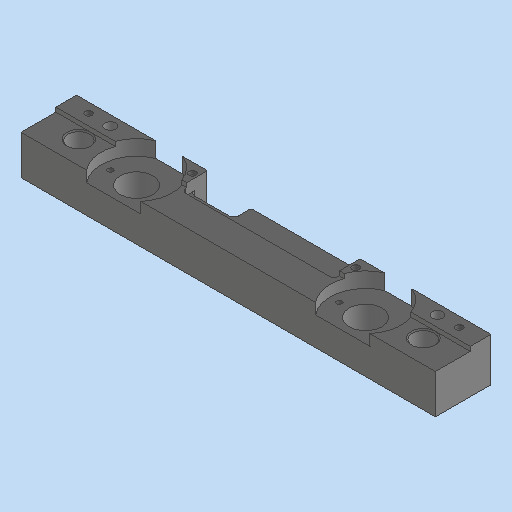
# Autodesk Inventor part: MM0937AN100_G16_150
Saved by Autodesk Inventor 2023.3 (Build 273359000, 359)
## iProperties
Created: 2024-03-12
Part Number: MM0937AN100_G16_150
Material: 1.2379 X155CrVMo12-1
Description: =<RBPARTNOTITLE2>
Document SubType Name: Modeling
Designer: FSM9BW
Mass: 534.69 g
Surface Area: 204.971 cm^2
Volume: 68.1134 cm^3
Density: 7.85 g/cm^3
Appearance: Stahl - rostfrei AnP
RBPARTMADEOF: 20 x 25,5 x 190 (FM)
RBDRAWINGMISSINGSPEC: --
AnP_Kategorie: 1
RBPARTNOTITLE2: Anfertigungsteil
RBSURFACE: plasma nitrided 1000 HV, Nht 0,1 + 0,1
RBPARTNOTITLE1: manufactured part
RBSURFACE2: plasmanitriert 1000 HV, Nht 0,1 + 0,1
AnP_Material: =<Material>
RBMATERIAL: =<Material>
RBMATNO: =<Part Number>
RBPARTNO: SIEHE MNR
MaxAbmaße: 20 x 25,5 x 190 (FM)
Author: FSM9BW
Keywords: =<RBPARTMADEOF>
Comments: =<RBSURFACE2>
Revision Number: 01
Autodesk Inventor part; units mm, degrees
ref_plane "YZ Plane" through (0, 0, 0) normal (1, 0, 0) x (0, 1, 0)
ref_plane "XZ Plane" through (0, 0, 0) normal (0, 1, 0) x (-1, 0, 0)
ref_plane "XY Plane" through (0, 0, 0) normal (0, 0, 1) x (1, 0, 0)
sketch "Skizze1" plane through (0, 0, 0) normal (0, 0, 1) x (1, 0, 0)
  line L0 (-95, 0) -> (95, 0)
  line L1 (95, 0) -> (95, 25.5)
  line L2 (95, 25.5) -> (-95, 25.5)
  line L3 (-95, 25.5) -> (-95, 0)
  line L4 (-133, 0) -> (133, 0) projected
  line L5 (0, -5.1) -> (0, 30.6) projected
  point P0 (0, 0)
  dimension "d0" = 190
  dimension "d1" = 25.5
  constraints: 8 end point, 2 parallel, 1 collinear, 1 horizontal, 1 perpendicular, 1 other
  measures "d0" distance of L0.start L0.end
  measures "d1" distance of L2.end L0.start
extrude "Extrusion1" add sketch "Skizze1" along normal mid plane 20
sketch "Skizze2" plane through (0, 0, 10) normal (0, 0, 1) x (1, 0, 0)
  line L0 (-95, 25.5) -> (-95, 0) projected
  line L1 (-95, 0) -> (95, 0) projected
  line L2 (95, 0) -> (95, 25.5) projected
  line L3 (95, 25.5) -> (-95, 25.5) projected
  line L4 (-35, 25.5) -> (35, 25.5)
  line L5 (35, 25.5) -> (35, 13.5)
  line L6 (35, 13.5) -> (-35, 13.5)
  line L7 (-35, 13.5) -> (-35, 25.5)
  line L8 (0, -5.1) -> (0, 30.6) projected
  point P0 (0, 0)
  dimension "d4" = 70
  dimension "d5" = 12
  constraints: 8 end point, 2 parallel, 1 horizontal, 1 perpendicular, 1 point on line, 1 other
  measures "d4" distance of L5.end L6.end
  measures "d5" distance of L6.end L4.start
extrude "Extrusion2" cut sketch "Skizze2" against normal blind 5 contours L3 L8 L6 L7 | L3 L5 L6 L8
sketch "Skizze3" plane through (0, 0, 10) normal (0, 0, 1) x (1, 0, 0)
  line L0 (35, 25.5) -> (35, 13.5) projected
  line L1 (35, 13.5) -> (-35, 13.5) projected
  line L2 (-35, 13.5) -> (-35, 25.5) projected
  line L3 (-35, 25.5) -> (-95, 25.5) projected
  line L4 (-95, 25.5) -> (-95, 0) projected
  line L5 (-95, 0) -> (95, 0) projected
  line L6 (95, 0) -> (95, 25.5) projected
  line L7 (95, 25.5) -> (35, 25.5) projected
  line L8 (-35, 25.5) -> (-15, 25.5)
  line L9 (-15, 25.5) -> (-15, 17.5)
  line L10 (-15, 17.5) -> (-35, 17.5)
  line L11 (-35, 17.5) -> (-35, 25.5)
  point P0 (0, 0)
  point P1 (-35, 17.5)
  dimension "d8" = 8
  dimension "d9" = 60
  dimension "d10" = 20
  constraints: 8 end point, 2 parallel, 1 horizontal, 1 perpendicular, 1 point on line
  measures "d8" distance of L10.end L8.start
  measures "d9" distance between parallel lines of L11 L4
  measures "d10" distance between parallel lines of L2 L9
extrude "Extrusion3" cut sketch "Skizze3" against normal through all contours L2 L8 L9 L10
sketch "Skizze4" plane through (0, 0, 10) normal (0, 0, 1) x (1, 0, 0)
  line L0 (35, 25.5) -> (35, 13.5) projected
  line L1 (35, 13.5) -> (-35, 13.5) projected
  line L2 (-35, 13.5) -> (-35, 25.5) projected
  line L3 (-35, 25.5) -> (-95, 25.5) projected
  line L4 (-95, 25.5) -> (-95, 0) projected
  line L5 (-95, 0) -> (95, 0) projected
  line L6 (95, 0) -> (95, 25.5) projected
  line L7 (95, 25.5) -> (35, 25.5) projected
  line L8 (-95, 0) -> (95, 0)
  line L9 (95, 0) -> (95, 16)
  line L10 (95, 16) -> (-95, 16)
  line L11 (-95, 16) -> (-95, 0)
  point P0 (0, 0)
  point P1 (-35, 10.5)
  point P2 (35, 10.5)
  dimension "d13" = 190
  dimension "d14" = 16
  constraints: 8 end point, 2 parallel, 1 horizontal, 1 perpendicular
  measures "d13" distance of L10.end L9.end
  measures "d14" distance of L9.end L8.end
extrude "Extrusion4" cut sketch "Skizze4" against normal blind 2 contours L10 L6 L5 L4 L2 L1 L0 | L0 L1 L2 L10
sketch "Skizze5" plane through (0, 0, 10) normal (0, 0, 1) x (1, 0, 0)
  line L0 (-95, 0) -> (95, 0) projected
  line L1 (-133, 0) -> (133, 0) projected
  point P0 (-79, 10.5)
  point P1 (79, 10.5)
  point P2 (0, 0)
  point P3 (0, 0)
  dimension "d45" = 10.5
  dimension "d50" = 79
  dimension "d51" = 79
  constraints: 1 horizontal alignment, 1 midpoint
  measures "d45" distance from line of point (-79, 10.5) L0
  measures "d50" horizontal distance of point (-79, 10.5) point (0, 0)
  measures "d51" horizontal distance of point (79, 10.5) point (0, 0)
hole "Bohrung1" at (-79, 10.5, 10) at (79, 10.5, 10) direction (0, 0, -1) diameter 10 end through all
sketch "Skizze10" plane through (0, 0, 10) normal (0, 0, 1) x (1, 0, 0)
  line L0 (95, 0) -> (-95, 0) projected
  point P0 (0, 0)
  point P1 (-52.5, 10.5)
  point P2 (52.5, 10.5)
  point P3 (0, 0)
  point P4 (0, 0)
  point P5 (0, 0)
  point P6 (0, 0)
  dimension "d52" = 10.5
  dimension "d53" = 10.5
  dimension "d54" = 52.5
  dimension "d55" = 52.5
  constraints: 4 midpoint
  measures "d52" vertical distance of point (-52.5, 10.5) point (0, 0)
  measures "d53" vertical distance of point (52.5, 10.5) point (0, 0)
  measures "d54" horizontal distance of point (-52.5, 10.5) point (0, 0)
  measures "d55" horizontal distance of point (52.5, 10.5) point (0, 0)
hole "Bohrung2" at (-52.5, 10.5, 10) at (52.5, 10.5, 10) direction (0, 0, -1) diameter 15 end through all counterbore diameter 32.5 counterbore depth 7
sketch "Skizze12" plane through (-64.9021, 0, 3) normal (0, 0, 1) x (1, 0, 0)
  circle A0 centre (12.4021, 10.5) radius 7.5 projected
  circle A1 centre (117.4021, 10.5) radius 7.5 projected
  point P0 (64.9021, 0)
  point P1 (0.4021, 10.5)
  point P2 (24.4021, 10.5)
  point P3 (105.4021, 10.5)
  point P4 (129.4021, 10.5)
  dimension "d63" = 24
  dimension "d64" = 12
  dimension "d65" = 24
  dimension "d66" = 12
  constraints: 4 horizontal alignment
  measures "d63" distance of point (129.402, 10.5) point (105.402, 10.5)
  measures "d64" distance of point (105.402, 10.5) A1.centre
  measures "d65" distance of point (0.402, 10.5) point (24.402, 10.5)
  measures "d66" distance of point (24.402, 10.5) A0.centre
hole "Bohrung3" at (-64.5, 10.5, 3) at (-40.5, 10.5, 3) at (40.5, 10.5, 3) at (64.5, 10.5, 3) direction (0, 0, -1) diameter 2.459 end through all thread size "M3x0.5" designation "M3" class "6H" standard "ISO Metric profile"
sketch "Skizze13" plane through (0, 0, -10) normal (0, 0, -1) x (-1, 0, 0)
  circle A0 centre (-79, 10.5) radius 5 projected
  circle A1 centre (79, 10.5) radius 5 projected
  point P0 (0, 0)
  constraints: 2 coincident
hole "Bohrung4" at (79, 10.5, -10) at (-79, 10.5, -10) direction (0, 0, 1) diameter 10.106 depth 10 tip angle 118 thread size "M12x1.75" designation "M12" class "6H" standard "ISO Metric profile"
sketch "Skizze14" plane through (0, 0, 10) normal (0, 0, 1) x (1, 0, 0)
  line L0 (-58.75, 25.5) -> (-95, 25.5) projected
  point P0 (0, 0)
  point P1 (-85, 21)
  point P2 (85, 21)
  point P3 (-37.4, 21)
  point P4 (37.4, 21)
  dimension "d82" = 21
  dimension "d83" = 85
  dimension "d84" = 85
  dimension "d92" = 37.4
  dimension "d93" = 37.4
  constraints: 3 horizontal alignment
  measures "d82" vertical distance of point (-85, 21) point (0, 0)
  measures "d83" horizontal distance of point (-85, 21) point (0, 0)
  measures "d84" horizontal distance of point (85, 21) point (0, 0)
  measures "d92" horizontal distance of point (-37.4, 21) point (0, 0)
  measures "d93" horizontal distance of point (37.4, 21) point (0, 0)
hole "Bohrung5" at (-85, 21, 10) at (85, 21, 10) at (-37.4, 21, 10) at (37.4, 21, 10) direction (0, 0, -1) diameter 3.242 depth 11.8 tip angle 118 thread size "M4x0.7" designation "M4" class "6H" standard "ISO Metric profile"
sketch "Skizze16" plane through (0, 0, 10) normal (0, 0, 1) x (1, 0, 0)
  circle A0 centre (-85, 21) radius 1.621 projected
  circle A1 centre (85, 21) radius 1.621 projected
  point P0 (0, 0)
  point P1 (-75, 21)
  point P2 (75, 21)
  dimension "d95" = 75
  dimension "d96" = 75
  constraints: 2 horizontal alignment
  measures "d95" horizontal distance of point (-75, 21) point (0, 0)
  measures "d96" horizontal distance of point (75, 21) point (0, 0)
hole "Bohrung6" at (-75, 21, 10) at (75, 21, 10) direction (0, 0, -1) diameter 5 depth 6 tip angle 118
fillet "Rundung1" radius 2 4 edges at (-35, 17.5, -2.5) (-15, 17.5, -2.5) (-35, 13.5, 6.5) (35, 13.5, 6.5)
chamfer "Fase1" distance 0.5 angle 45 3 edges at (-35, 25.5, 0) (-15, 25.5, -2.5) (35, 25.5, 7.5)
chamfer "Fase2" distance 0.5 angle 45 2 edges at (-79, 15.5, 8) (79, 15.5, 8)
